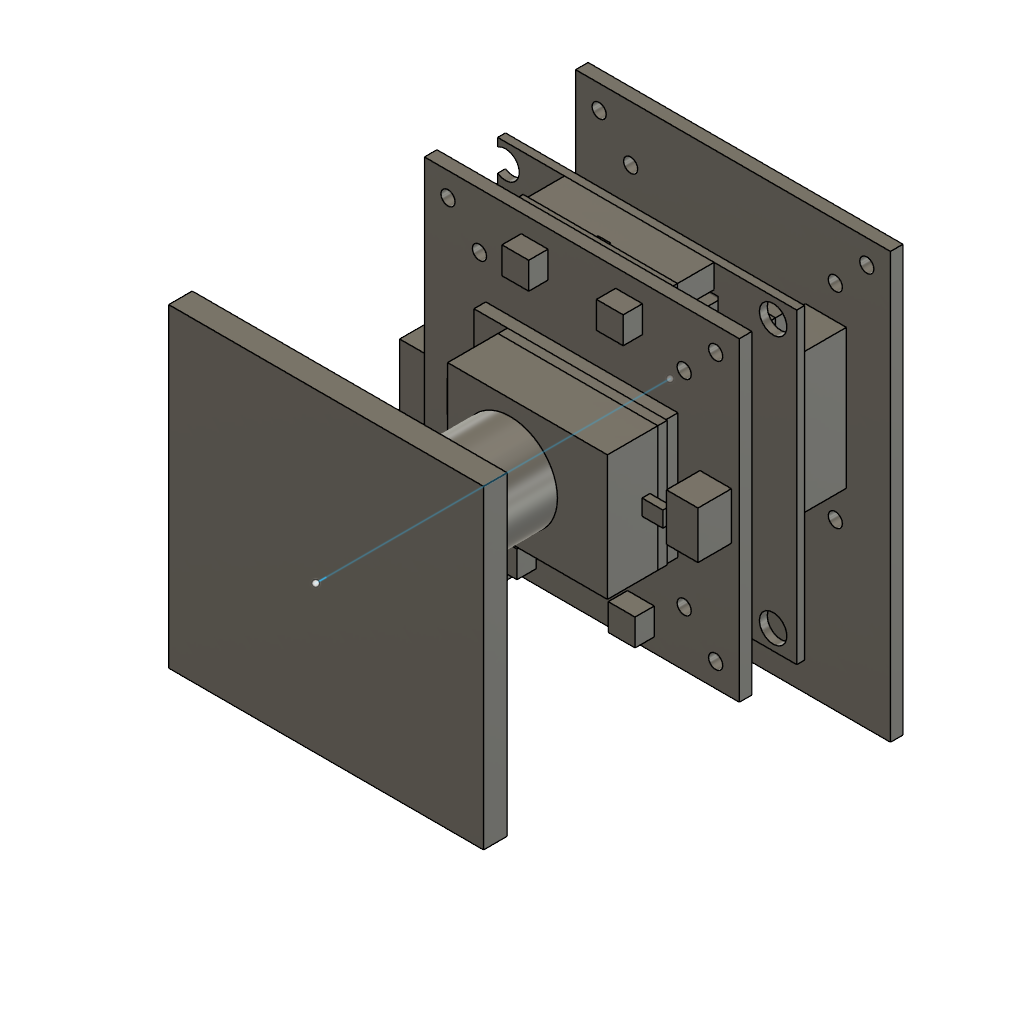
M001_stack_reference (Autodesk Fusion 360 design; units mm, degrees)
part number: 2026-11-26-16-17-13-301
part number: 2026-11-26-16-17-34-578
part number: 2026-11-26-16-17-34-690
part number: 2026-11-26-16-17-34-799
part number: 2026-11-26-16-17-34-957
part number: 2026-11-26-16-17-35-481
part number: 2026-11-26-16-17-36-242
part number: 2026-11-26-16-18-00-802
part number: 2026-11-26-16-54-47-917
part number: 2026-11-26-16-54-48-481
part number: 2026-11-26-16-54-49-083
part number: 2026-11-26-16-54-49-733
part number: 2026-11-26-16-54-51-577
part number: 2026-11-26-16-54-52-375
part number: 2026-11-26-16-54-53-304
part number: 2026-11-26-16-54-54-303
part number: 2026-11-26-17-14-53-023
part number: 2026-11-26-17-14-54-048
part number: 2026-11-26-17-14-55-387
part number: 2026-11-26-17-14-57-169
part number: 2026-11-26-17-14-57-799
part number: 2026-11-26-17-14-58-396
part number: 2026-11-26-17-42-16-332
part number: 2026-11-26-17-42-20-928
part number: 2026-11-26-17-42-21-584
part number: 2026-11-26-17-44-47-207
part number: 2026-11-26-17-44-48-247
part number: 2026-11-26-17-44-49-089
part number: 2026-11-26-17-44-49-752
part number: 2026-11-26-21-12-26-207
part number: 2026-11-26-21-12-26-805
part number: 2026-11-26-21-12-27-357
Autodesk Fusion 360 part; units mm, degrees
ref_plane "작업 평면1" through (0, 0, -1.26) normal (0, 0, 1) x (1, 0, 0) in component "CORE_BOT_KEEPIN"
sketch "스케치1" plane through (0, 0, -1.26) normal (0, 0, 1) x (1, 0, 0) in component "CORE_BOT_KEEPIN"
  line L0 (15, 15) -> (-15, 15)
  line L1 (-15, 15) -> (-15, -15)
  line L2 (-15, -15) -> (15, -15)
  line L3 (15, -15) -> (15, 15)
extrude "돌출1" add sketch "스케치1" along normal blind 1.26 makes body 1 in component "CORE_BOT_KEEPIN"
ref_plane "작업 평면1" through (0, 0, -8) normal (0, 0, 1) x (1, 0, 0) in component "J2_MATED_ENVELOPE"
sketch "스케치1 (2)" plane through (0, 0, -8) normal (0, 0, 1) x (1, 0, 0) in component "J2_MATED_ENVELOPE"
  line L0 (14.4, 8.85) -> (9.2, 8.85)
  line L1 (9.2, 8.85) -> (9.2, -8.85)
  line L2 (9.2, -8.85) -> (14.4, -8.85)
  line L3 (14.4, -8.85) -> (14.4, 8.85)
extrude "돌출1'" add sketch "스케치1 (2)" along normal blind 8 separate body makes body 2 in component "J2_MATED_ENVELOPE"
ref_plane "작업 평면1" through (0, 0, 0) normal (0, 0, 1) x (1, 0, 0) in component "CORE_ENVELOPE_30x30"
sketch "스케치1 (3)" plane through (0, 0, 0) normal (0, 0, 1) x (1, 0, 0) in component "CORE_ENVELOPE_30x30"
  line L0 (15, 15) -> (-15, 15)
  line L1 (-15, 15) -> (-15, -15)
  line L2 (-15, -15) -> (15, -15)
  line L3 (15, -15) -> (15, 15)
  circle A0 centre (13, 13) radius 1
  circle A1 centre (13, -13) radius 1
  circle A2 centre (-13, 13) radius 1
extrude "돌출1''" add sketch "스케치1 (3)" along normal blind 1.6 separate body makes body 3 in component "CORE_ENVELOPE_30x30"
ref_plane "작업 평면1" through (0, 0, 1.6) normal (0, 0, 1) x (1, 0, 0) in component "CORE_TOP_KEEPIN"
sketch "스케치1 (4)" plane through (0, 0, 1.6) normal (0, 0, 1) x (1, 0, 0) in component "CORE_TOP_KEEPIN"
  line L0 (15, 15) -> (-15, 15)
  line L1 (-15, 15) -> (-15, -15)
  line L2 (-15, -15) -> (15, -15)
  line L3 (15, -15) -> (15, 15)
extrude "돌출1'''" add sketch "스케치1 (4)" along normal blind 0.92 separate body makes body 4 in component "CORE_TOP_KEEPIN"
ref_plane "작업 평면1" through (0, 0, 9.6) normal (0, 0, 1) x (1, 0, 0) in component "FRONT_40x40"
sketch "스케치1 (5)" plane through (0, 0, 9.6) normal (0, 0, 1) x (1, 0, 0) in component "FRONT_40x40"
  line L0 (20, 20) -> (-20, 20)
  line L1 (-20, 20) -> (-20, -20)
  line L2 (-20, -20) -> (20, -20)
  line L3 (20, -20) -> (20, 20)
  circle A0 centre (13, 13) radius 0.9
  circle A1 centre (13, -13) radius 0.9
  circle A2 centre (-13, 13) radius 0.9
  circle A3 centre (-17, -17) radius 0.9
  circle A4 centre (17, 17) radius 0.9
  circle A5 centre (17, -17) radius 0.9
  circle A6 centre (-17, 17) radius 0.9
  circle A7 centre (10, 0) radius 0.9
  circle A8 centre (-10, 0) radius 0.9
extrude "돌출1''''" add sketch "스케치1 (5)" along normal blind 1.6 separate body makes body 5 in component "FRONT_40x40"
ref_plane "작업 평면1" through (0, 0, 40.685) normal (0, 0, 1) x (1, 0, 0) in component "WINDOW_PMMA"
sketch "스케치1 (6)" plane through (0, 0, 40.685) normal (0, 0, 1) x (1, 0, 0) in component "WINDOW_PMMA"
  line L0 (20, 20) -> (-20, 20)
  line L1 (-20, 20) -> (-20, -20)
  line L2 (-20, -20) -> (20, -20)
  line L3 (20, -20) -> (20, 20)
extrude "돌출1'''''" add sketch "스케치1 (6)" along normal blind 3 separate body makes body 6 in component "WINDOW_PMMA"
sketch "스케치1 (7)" plane through (0, 0, 0) normal (0, 1, 0) x (1, 0, 0)
  line L0 (0, 0) -> (0, -45)
ref_plane "작업 평면1" through (0, 0, 1.6) normal (0, 0, 1) x (1, 0, 0) in component "J1_MATED_ENVELOPE"
sketch "스케치1 (8)" plane through (0, 0, 1.6) normal (0, 0, 1) x (1, 0, 0) in component "J1_MATED_ENVELOPE"
  line L0 (8.85, 14.41) -> (-8.85, 14.41)
  line L1 (-8.85, 14.41) -> (-8.85, 9.19)
  line L2 (-8.85, 9.19) -> (8.85, 9.19)
  line L3 (8.85, 9.19) -> (8.85, 14.41)
extrude "돌출1''''''" add sketch "스케치1 (8)" along normal blind 8 separate body makes body 7 in component "J1_MATED_ENVELOPE"
ref_plane "작업 평면1" through (0, 0, 11.2) normal (0, 0, 1) x (1, 0, 0) in component "PEDESTAL"
sketch "스케치1 (9)" plane through (0, 0, 11.2) normal (0, 0, 1) x (1, 0, 0) in component "PEDESTAL"
  line L0 (-6.6, -6.6) -> (6.6, -6.6)
  line L1 (6.6, -6.6) -> (6.6, 6.6)
  line L2 (6.6, 6.6) -> (-6.6, 6.6)
  line L3 (-6.6, 6.6) -> (-6.6, -6.6)
  dimension "d117" = 13.2
  dimension "d118" = 13.2
  dimension "d119" = 6.6
  dimension "d120" = 6.6
  measures "d117" horizontal distance of L0.start L0.end
  measures "d118" vertical distance of L0.end L1.end
  measures "d119" horizontal distance of origin L0.start
  measures "d120" vertical distance of origin L0.start
extrude "돌출1'''''''" add sketch "스케치1 (9)" along normal blind 0.75 separate body makes body 8 in component "PEDESTAL"
ref_plane "작업 평면1" through (0, 0, 11.95) normal (0, 0, 1) x (1, 0, 0) in component "SENSOR_BLOCK_BXF4677"
sketch "스케치1 (10)" plane through (0, 0, 11.95) normal (0, 0, 1) x (1, 0, 0) in component "SENSOR_BLOCK_BXF4677"
  line L0 (-6.6, -6.6) -> (6.6, -6.6)
  line L1 (6.6, -6.6) -> (6.6, 6.6)
  line L2 (6.6, 6.6) -> (-6.6, 6.6)
  line L3 (-6.6, 6.6) -> (-6.6, -6.6)
  dimension "d125" = 13.2
  dimension "d126" = 13.2
  dimension "d127" = 6.6
  dimension "d128" = 6.6
  measures "d125" horizontal distance of L0.start L0.end
  measures "d126" vertical distance of L0.end L1.end
  measures "d127" horizontal distance of origin L0.start
  measures "d128" vertical distance of origin L0.start
extrude "돌출1''''''''" add sketch "스케치1 (10)" along normal blind 1.28 separate body makes body 9 in component "SENSOR_BLOCK_BXF4677"
ref_plane "작업 평면1" through (0, 0, 12.35) normal (0, 0, 1) x (1, 0, 0) in component "FPC_3mm"
sketch "스케치1 (11)" plane through (0, 0, 12.35) normal (0, 0, 1) x (1, 0, 0) in component "FPC_3mm"
  line L0 (-3.8, -9.6) -> (3.8, -9.6)
  line L1 (3.8, -9.6) -> (3.8, -6.6)
  line L2 (3.8, -6.6) -> (-3.8, -6.6)
  line L3 (-3.8, -6.6) -> (-3.8, -9.6)
  dimension "d133" = 7.6
  dimension "d134" = 3
  dimension "d135" = 3.8
  dimension "d136" = 9.6
  measures "d133" horizontal distance of L0.start L0.end
  measures "d134" vertical distance of L0.end L1.end
  measures "d135" horizontal distance of origin L0.start
  measures "d136" vertical distance of origin L0.start
extrude "돌출1'''''''''" add sketch "스케치1 (11)" along normal blind 0.12 separate body makes body 10 in component "FPC_3mm"
ref_plane "작업 평면1" through (0, 0, 11.2) normal (0, 0, 1) x (1, 0, 0) in component "DF30_SITE"
sketch "스케치1 (12)" plane through (0, 0, 11.2) normal (0, 0, 1) x (1, 0, 0) in component "DF30_SITE"
  line L0 (-3.8, -14.4) -> (3.8, -14.4)
  line L1 (3.8, -14.4) -> (3.8, -9.6)
  line L2 (3.8, -9.6) -> (-3.8, -9.6)
  line L3 (-3.8, -9.6) -> (-3.8, -14.4)
  dimension "d141" = 7.6
  dimension "d142" = 4.8
  dimension "d143" = 3.8
  dimension "d144" = 14.4
  measures "d141" horizontal distance of L0.start L0.end
  measures "d142" vertical distance of L0.end L1.end
  measures "d143" horizontal distance of origin L0.start
  measures "d144" vertical distance of origin L0.start
extrude "돌출1''''''''''" add sketch "스케치1 (12)" along normal blind 1.15 separate body makes body 11 in component "DF30_SITE"
ref_plane "작업 평면1" through (0, 0, 11.2) normal (0, 0, 1) x (1, 0, 0) in component "LED_A1"
sketch "스케치1 (13)" plane through (0, 0, 11.2) normal (0, 0, 1) x (1, 0, 0) in component "LED_A1"
  line L0 (-7.7, 14.3) -> (-4.3, 14.3)
  line L1 (-4.3, 14.3) -> (-4.3, 17.7)
  line L2 (-4.3, 17.7) -> (-7.7, 17.7)
  line L3 (-7.7, 17.7) -> (-7.7, 14.3)
  dimension "d160" = 3.4
  dimension "d161" = 3.4
  dimension "d162" = 7.7
  dimension "d163" = 14.3
  measures "d160" horizontal distance of L0.start L0.end
  measures "d161" vertical distance of L0.end L1.end
  measures "d162" horizontal distance of origin L0.start
  measures "d163" vertical distance of origin L0.start
extrude "돌출1'''''''''''" add sketch "스케치1 (13)" along normal blind 2.445 separate body makes body 12 in component "LED_A1"
ref_plane "작업 평면1" through (0, 0, 11.2) normal (0, 0, 1) x (1, 0, 0) in component "LED_A2"
sketch "스케치1 (14)" plane through (0, 0, 11.2) normal (0, 0, 1) x (1, 0, 0) in component "LED_A2"
  line L0 (4.3, 14.3) -> (7.7, 14.3)
  line L1 (7.7, 14.3) -> (7.7, 17.7)
  line L2 (7.7, 17.7) -> (4.3, 17.7)
  line L3 (4.3, 17.7) -> (4.3, 14.3)
  dimension "d168" = 3.4
  dimension "d169" = 3.4
  dimension "d170" = 4.3
  dimension "d171" = 14.3
  measures "d168" horizontal distance of L0.start L0.end
  measures "d169" vertical distance of L0.end L1.end
  measures "d170" horizontal distance of origin L0.start
  measures "d171" vertical distance of origin L0.start
extrude "돌출1''''''''''''" add sketch "스케치1 (14)" along normal blind 2.445 separate body makes body 13 in component "LED_A2"
ref_plane "작업 평면1" through (0, 0, 11.2) normal (0, 0, 1) x (1, 0, 0) in component "LED_B1_DNP"
sketch "스케치1 (15)" plane through (0, 0, 11.2) normal (0, 0, 1) x (1, 0, 0) in component "LED_B1_DNP"
  line L0 (-9.2, -18.2) -> (-5.8, -18.2)
  line L1 (-5.8, -18.2) -> (-5.8, -14.8)
  line L2 (-5.8, -14.8) -> (-9.2, -14.8)
  line L3 (-9.2, -14.8) -> (-9.2, -18.2)
  dimension "d176" = 3.4
  dimension "d177" = 3.4
  dimension "d178" = 9.2
  dimension "d179" = 18.2
  measures "d176" horizontal distance of L0.start L0.end
  measures "d177" vertical distance of L0.end L1.end
  measures "d178" horizontal distance of origin L0.start
  measures "d179" vertical distance of origin L0.start
extrude "돌출1'''''''''''''" add sketch "스케치1 (15)" along normal blind 2.445 separate body makes body 14 in component "LED_B1_DNP"
ref_plane "작업 평면1" through (0, 0, 11.2) normal (0, 0, 1) x (1, 0, 0) in component "LED_B2_DNP"
sketch "스케치1 (16)" plane through (0, 0, 11.2) normal (0, 0, 1) x (1, 0, 0) in component "LED_B2_DNP"
  line L0 (5.8, -18.2) -> (9.2, -18.2)
  line L1 (9.2, -18.2) -> (9.2, -14.8)
  line L2 (9.2, -14.8) -> (5.8, -14.8)
  line L3 (5.8, -14.8) -> (5.8, -18.2)
  dimension "d184" = 3.4
  dimension "d185" = 3.4
  dimension "d186" = 5.8
  dimension "d187" = 18.2
  measures "d184" horizontal distance of L0.start L0.end
  measures "d185" vertical distance of L0.end L1.end
  measures "d186" horizontal distance of origin L0.start
  measures "d187" vertical distance of origin L0.start
extrude "돌출1''''''''''''''" add sketch "스케치1 (16)" along normal blind 2.445 separate body makes body 15 in component "LED_B2_DNP"
ref_plane "작업 평면1" through (0, 0, 11.2) normal (0, 0, 1) x (1, 0, 0) in component "HOLDER_SPACER_FRAME"
sketch "스케치1 (17)" plane through (0, 0, 11.2) normal (0, 0, 1) x (1, 0, 0) in component "HOLDER_SPACER_FRAME"
  line L0 (-12.2, -7.95) -> (-4.2, -7.95)
  line L1 (-4.2, -7.95) -> (-4.2, -7.2)
  line L2 (-4.2, -7.2) -> (-7.2, -7.2)
  line L3 (-7.2, -7.2) -> (-7.2, 7.2)
  line L4 (-7.2, 7.2) -> (7.2, 7.2)
  line L5 (7.2, 7.2) -> (7.2, -7.2)
  line L6 (7.2, -7.2) -> (4.2, -7.2)
  line L7 (4.2, -7.2) -> (4.2, -7.95)
  line L8 (4.2, -7.95) -> (12.2, -7.95)
  line L9 (12.2, -7.95) -> (12.2, 7.95)
  line L10 (12.2, 7.95) -> (-12.2, 7.95)
  line L11 (-12.2, 7.95) -> (-12.2, -7.95)
  circle A0 centre (10, 0) radius 0.85
  circle A1 centre (-10, 0) radius 0.85
extrude "돌출1'''''''''''''''" add sketch "스케치1 (17)" along normal blind 1.5 separate body makes body 16 in component "HOLDER_SPACER_FRAME"
ref_plane "작업 평면1" through (0, 0, 12.7) normal (0, 0, 1) x (1, 0, 0) in component "CLA216_ICR"
sketch "스케치1 (18)" plane through (0, 0, 12.7) normal (0, 0, 1) x (1, 0, 0) in component "CLA216_ICR"
  line L0 (-7.95, -7.95) -> (12.35, -7.95)
  line L1 (12.35, -7.95) -> (12.35, 7.95)
  line L2 (12.35, 7.95) -> (-7.95, 7.95)
  line L3 (-7.95, 7.95) -> (-7.95, -7.95)
  line L4 (-7.05, -7.05) -> (7.05, -7.05)
  line L5 (7.05, -7.05) -> (7.05, 7.05)
  line L6 (7.05, 7.05) -> (-7.05, 7.05)
  line L7 (-7.05, 7.05) -> (-7.05, -7.05)
extrude "돌출1''''''''''''''''" add sketch "스케치1 (18)" along normal blind 1.2 separate body makes body 17 in component "CLA216_ICR"
ref_plane "작업 평면2" through (0, 0, 13.9) normal (0, 0, 1) x (1, 0, 0) in component "CLA216_ICR"
sketch "스케치2" plane through (0, 0, 13.9) normal (0, 0, 1) x (1, 0, 0) in component "CLA216_ICR"
  line L0 (-7.95, -7.95) -> (12.35, -7.95)
  line L1 (12.35, -7.95) -> (12.35, 7.95)
  line L2 (12.35, 7.95) -> (-7.95, 7.95)
  line L3 (-7.95, 7.95) -> (-7.95, -7.95)
  circle A0 centre (0, 0) radius 6
extrude "돌출2" add sketch "스케치2" along normal blind 6.4 separate body makes body 18 in component "CLA216_ICR"
ref_plane "작업 평면3" through (0, 0, 12.7) normal (0, 0, 1) x (1, 0, 0) in component "CLA216_ICR"
sketch "스케치3" plane through (0, 0, 12.7) normal (0, 0, 1) x (1, 0, 0) in component "CLA216_ICR"
  line L0 (-12.2, -2) -> (-7.95, -2)
  line L1 (-7.95, -2) -> (-7.95, 2)
  line L2 (-7.95, 2) -> (-12.2, 2)
  line L3 (-12.2, 2) -> (-12.2, -2)
  circle A0 centre (-10, 0) radius 0.85
extrude "돌출3" add sketch "스케치3" along normal blind 3.4 separate body makes body 19 in component "CLA216_ICR"
ref_plane "작업 평면1" through (0, 0, 15.985) normal (0, 0, 1) x (1, 0, 0) in component "LENS_CIL093"
sketch "스케치1 (19)" plane through (0, 0, 15.985) normal (0, 0, 1) x (1, 0, 0) in component "LENS_CIL093"
  circle A0 centre (0, 0) radius 6
extrude "돌출1'''''''''''''''''" add sketch "스케치1 (19)" along normal blind 13.2 separate body makes body 20 in component "LENS_CIL093"
ref_plane "작업 평면2" through (0, 0, 29.185) normal (0, 0, 1) x (1, 0, 0) in component "LENS_CIL093"
sketch "스케치2 (2)" plane through (0, 0, 29.185) normal (0, 0, 1) x (1, 0, 0) in component "LENS_CIL093"
  circle A0 centre (0, 0) radius 7
extrude "돌출2'" add sketch "스케치2 (2)" along normal blind 4.2 separate body makes body 21 in component "LENS_CIL093"
ref_plane "작업 평면3" through (0, 0, 33.385) normal (0, 0, 1) x (1, 0, 0) in component "LENS_CIL093"
sketch "스케치3 (2)" plane through (0, 0, 33.385) normal (0, 0, 1) x (1, 0, 0) in component "LENS_CIL093"
  circle A0 centre (0, 0) radius 9
extrude "돌출3'" add sketch "스케치3 (2)" along normal blind 5.4 separate body makes body 22 in component "LENS_CIL093"
ref_plane "작업 평면4" through (0, 0, 38.785) normal (0, 0, 1) x (1, 0, 0) in component "LENS_CIL093"
sketch "스케치4" plane through (0, 0, 38.785) normal (0, 0, 1) x (1, 0, 0) in component "LENS_CIL093"
  circle A0 centre (0, 0) radius 5
extrude "돌출4" add sketch "스케치4" along normal blind 1.4 separate body makes body 23 in component "LENS_CIL093"
ref_plane "작업 평면1" through (0, 0, 38.785) normal (0, 0, 1) x (1, 0, 0) in component "LIGHT_COLLAR"
sketch "스케치1 (20)" plane through (0, 0, 38.785) normal (0, 0, 1) x (1, 0, 0) in component "LIGHT_COLLAR"
  circle A0 centre (0, 0) radius 10
  circle A1 centre (0, 0) radius 7
extrude "돌출1''''''''''''''''''" add sketch "스케치1 (20)" along normal blind 1.9 separate body makes body 24 in component "LIGHT_COLLAR"
ref_plane "작업 평면1" through (0, 0, 14.9) normal (0, 0, 1) x (1, 0, 0) in component "ICR_LEAD_PATH"
sketch "스케치1 (21)" plane through (0, 0, 14.9) normal (0, 0, 1) x (1, 0, 0) in component "ICR_LEAD_PATH"
  line L0 (12.35, -1) -> (15, -1)
  line L1 (15, -1) -> (15, 1)
  line L2 (15, 1) -> (12.35, 1)
  line L3 (12.35, 1) -> (12.35, -1)
extrude "돌출1'''''''''''''''''''" add sketch "스케치1 (21)" along normal blind 1 separate body makes body 25 in component "ICR_LEAD_PATH"
ref_plane "작업 평면1" through (0, 0, 11.2) normal (0, 0, 1) x (1, 0, 0) in component "J_ICR_SITE"
sketch "스케치1 (22)" plane through (0, 0, 11.2) normal (0, 0, 1) x (1, 0, 0) in component "J_ICR_SITE"
  line L0 (15, -3) -> (19, -3)
  line L1 (19, -3) -> (19, 3)
  line L2 (19, 3) -> (15, 3)
  line L3 (15, 3) -> (15, -3)
extrude "돌출1''''''''''''''''''''" add sketch "스케치1 (22)" along normal blind 4.25 separate body makes body 26 in component "J_ICR_SITE"
ref_plane "작업 평면1" through (0, 0, 2.9) normal (0, 0, 1) x (1, 0, 0) in component "AL_SPREADER_TAB_PX"
sketch "스케치1 (23)" plane through (0, 0, 2.9) normal (0, 0, 1) x (1, 0, 0) in component "AL_SPREADER_TAB_PX"
  line L0 (-18, -19.5) -> (20, -19.5)
  line L1 (20, -19.5) -> (20, 19.5)
  line L2 (20, 19.5) -> (-18, 19.5)
  line L3 (-18, 19.5) -> (-18, -19.5)
  line L4 (-10, 8) -> (10, 8)
  line L5 (10, 8) -> (10, 16)
  line L6 (10, 16) -> (-10, 16)
  line L7 (-10, 16) -> (-10, 8)
  circle A0 centre (13, 13) radius 0.9
  circle A1 centre (13, -13) radius 0.9
  circle A2 centre (-13, 13) radius 0.9
  circle A3 centre (-17, -17) radius 0.9
  circle A4 centre (17, 17) radius 1.75
  circle A5 centre (17, -17) radius 1.75
  circle A6 centre (-17, 17) radius 1.75
extrude "돌출1'''''''''''''''''''''" add sketch "스케치1 (23)" along normal blind 1 separate body contours L0 L1 L2 L3 A6 makes body 27 in component "AL_SPREADER_TAB_PX"
ref_plane "작업 평면1" through (0, 0, 3.9) normal (0, 0, 1) x (1, 0, 0) in component "THERMAL_PILLAR_A"
sketch "스케치1 (24)" plane through (0, 0, 3.9) normal (0, 0, 1) x (1, 0, 0) in component "THERMAL_PILLAR_A"
  line L0 (-9.5, 16.5) -> (9.5, 16.5)
  line L1 (9.5, 16.5) -> (9.5, 19.5)
  line L2 (9.5, 19.5) -> (-9.5, 19.5)
  line L3 (-9.5, 19.5) -> (-9.5, 16.5)
extrude "돌출1''''''''''''''''''''''" add sketch "스케치1 (24)" along normal blind 4.95 separate body makes body 28 in component "THERMAL_PILLAR_A"
ref_plane "작업 평면1" through (0, 0, 3.9) normal (0, 0, 1) x (1, 0, 0) in component "THERMAL_PILLAR_B"
sketch "스케치1 (25)" plane through (0, 0, 3.9) normal (0, 0, 1) x (1, 0, 0) in component "THERMAL_PILLAR_B"
  line L0 (-12, -19.5) -> (-6, -19.5)
  line L1 (-6, -19.5) -> (-6, -13.5)
  line L2 (-6, -13.5) -> (-12, -13.5)
  line L3 (-12, -13.5) -> (-12, -19.5)
  line L4 (6, -19.5) -> (12, -19.5)
  line L5 (12, -19.5) -> (12, -13.5)
  line L6 (12, -13.5) -> (6, -13.5)
  line L7 (6, -13.5) -> (6, -19.5)
extrude "돌출1'''''''''''''''''''''''" add sketch "스케치1 (25)" along normal blind 4.95 separate body makes body 29 at (-10, -15.5, 3.9) makes body 30 at (8, -15.5, 3.9) in component "THERMAL_PILLAR_B"
ref_plane "작업 평면1" through (0, 0, -9.6) normal (0, 0, 1) x (1, 0, 0) in component "CARRIER_40x54"
sketch "스케치1 (26)" plane through (0, 0, -9.6) normal (0, 0, 1) x (1, 0, 0) in component "CARRIER_40x54"
  line L0 (-20, -34) -> (20, -34)
  line L1 (20, -34) -> (20, 20)
  line L2 (20, 20) -> (-20, 20)
  line L3 (-20, 20) -> (-20, -34)
  circle A0 centre (13, 13) radius 0.9
  circle A1 centre (13, -13) radius 0.9
  circle A2 centre (-13, 13) radius 0.9
  circle A3 centre (-17, -17) radius 0.9
  circle A4 centre (17, 17) radius 0.9
  circle A5 centre (-17, 17) radius 0.9
extrude "돌출1''''''''''''''''''''''''" add sketch "스케치1 (26)" along normal blind 1.6 separate body makes body 31 in component "CARRIER_40x54"
ref_plane "작업 평면1" through (0, 0, -8) normal (0, 0, 1) x (1, 0, 0) in component "GH6P_CARRIER_TOP"
sketch "스케치1 (27)" plane through (0, 0, -8) normal (0, 0, 1) x (1, 0, 0) in component "GH6P_CARRIER_TOP"
  line L0 (-19, -30.8) -> (-13.5, -30.8)
  line L1 (-13.5, -30.8) -> (-13.5, -19.3)
  line L2 (-13.5, -19.3) -> (-19, -19.3)
  line L3 (-19, -19.3) -> (-19, -30.8)
extrude "돌출1'''''''''''''''''''''''''" add sketch "스케치1 (27)" along normal blind 4.25 separate body makes body 32 in component "GH6P_CARRIER_TOP"
ref_plane "작업 평면1" through (0, 0, 5.35) normal (0, 0, 1) x (1, 0, 0) in component "GH6P_FRONT_BOT"
sketch "스케치1 (28)" plane through (0, 0, 5.35) normal (0, 0, 1) x (1, 0, 0) in component "GH6P_FRONT_BOT"
  line L0 (-19, -14.7) -> (-13.5, -14.7)
  line L1 (-13.5, -14.7) -> (-13.5, -3.2)
  line L2 (-13.5, -3.2) -> (-19, -3.2)
  line L3 (-19, -3.2) -> (-19, -14.7)
extrude "돌출1''''''''''''''''''''''''''" add sketch "스케치1 (28)" along normal blind 4.25 separate body makes body 33 in component "GH6P_FRONT_BOT"
ref_plane "작업 평면1" through (0, 0, -8) normal (0, 0, 1) x (1, 0, 0) in component "HARNESS_CORRIDOR_MX"
sketch "스케치1 (29)" plane through (0, 0, -8) normal (0, 0, 1) x (1, 0, 0) in component "HARNESS_CORRIDOR_MX"
  line L0 (-24.75, -30.8) -> (-19, -30.8)
  line L1 (-19, -30.8) -> (-19, -3.2)
  line L2 (-19, -3.2) -> (-24.75, -3.2)
  line L3 (-24.75, -3.2) -> (-24.75, -30.8)
extrude "돌출1'''''''''''''''''''''''''''" add sketch "스케치1 (29)" along normal blind 17.6 separate body makes body 34 in component "HARNESS_CORRIDOR_MX"
ref_plane "작업 평면1" through (0, 0, 8.85) normal (0, 0, 1) x (1, 0, 0) in component "INS_PAD_A"
sketch "스케치1 (30)" plane through (0, 0, 8.85) normal (0, 0, 1) x (1, 0, 0) in component "INS_PAD_A"
  line L0 (-9.8, 16.2) -> (9.8, 16.2)
  line L1 (9.8, 16.2) -> (9.8, 19.8)
  line L2 (9.8, 19.8) -> (-9.8, 19.8)
  line L3 (-9.8, 19.8) -> (-9.8, 16.2)
extrude "돌출1''''''''''''''''''''''''''''" add sketch "스케치1 (30)" along normal blind 0.75 separate body makes body 35 in component "INS_PAD_A"
ref_plane "작업 평면1" through (0, 0, 8.85) normal (0, 0, 1) x (1, 0, 0) in component "INS_PAD_B1"
sketch "스케치1 (31)" plane through (0, 0, 8.85) normal (0, 0, 1) x (1, 0, 0) in component "INS_PAD_B1"
  line L0 (-12.3, -19.8) -> (-6, -19.8)
  line L1 (-6, -19.8) -> (-6, -13.2)
  line L2 (-6, -13.2) -> (-12.3, -13.2)
  line L3 (-12.3, -13.2) -> (-12.3, -19.8)
extrude "돌출1'''''''''''''''''''''''''''''" add sketch "스케치1 (31)" along normal blind 0.75 separate body makes body 36 in component "INS_PAD_B1"
ref_plane "작업 평면1" through (0, 0, 8.85) normal (0, 0, 1) x (1, 0, 0) in component "INS_PAD_B2"
sketch "스케치1 (32)" plane through (0, 0, 8.85) normal (0, 0, 1) x (1, 0, 0) in component "INS_PAD_B2"
  line L0 (6, -19.8) -> (12.3, -19.8)
  line L1 (12.3, -19.8) -> (12.3, -13.2)
  line L2 (12.3, -13.2) -> (6, -13.2)
  line L3 (6, -13.2) -> (6, -19.8)
extrude "돌출1''''''''''''''''''''''''''''''" add sketch "스케치1 (32)" along normal blind 0.75 separate body makes body 37 in component "INS_PAD_B2"
ref_plane "작업 평면2" through (0, 0, 8.85) normal (0, 0, 1) x (1, 0, 0) in component "THERMAL_PILLAR_A"
sketch "스케치3 (3)" plane through (0, 0, 8.85) normal (0, 0, 1) x (1, 0, 0) in component "THERMAL_PILLAR_A"
  line L0 (-0.8, 16) -> (0.8, 16)
  line L1 (0.8, 16) -> (0.8, 20)
  line L2 (0.8, 20) -> (-0.8, 20)
  line L3 (-0.8, 20) -> (-0.8, 16)
extrude "RELIEF_SLOT_CUT" cut sketch "스케치3 (3)" against normal blind 0.5 bodies 28 in component "THERMAL_PILLAR_A"
component "CORE_BOT_KEEPIN" placed x (1, 0, 0) y (0, 1, 0) z (0, 0, 1) at (0, 0, 0)
component "J2_MATED_ENVELOPE" placed x (1, 0, 0) y (0, 1, 0) z (0, 0, 1) at (0, 0, 0)
component "CORE_ENVELOPE_30x30" placed x (1, 0, 0) y (0, 1, 0) z (0, 0, 1) at (0, 0, 0)
component "CORE_TOP_KEEPIN" placed x (1, 0, 0) y (0, 1, 0) z (0, 0, 1) at (0, 0, 0)
component "FRONT_40x40" placed x (1, 0, 0) y (0, 1, 0) z (0, 0, 1) at (0, 0, 0)
component "WINDOW_PMMA" placed x (1, 0, 0) y (0, 1, 0) z (0, 0, 1) at (0, 0, 0)
component "J1_MATED_ENVELOPE" placed x (1, 0, 0) y (0, 1, 0) z (0, 0, 1) at (0, 0, 0)
component "PEDESTAL" placed x (1, 0, 0) y (0, 1, 0) z (0, 0, 1) at (0, 0, 0)
component "SENSOR_BLOCK_BXF4677" placed x (1, 0, 0) y (0, 1, 0) z (0, 0, 1) at (0, 0, 0)
component "FPC_3mm" placed x (1, 0, 0) y (0, 1, 0) z (0, 0, 1) at (0, 0, 0)
component "DF30_SITE" placed x (1, 0, 0) y (0, 1, 0) z (0, 0, 1) at (0, 0, 0)
component "LED_A1" placed x (1, 0, 0) y (0, 1, 0) z (0, 0, 1) at (0, 0, 0)
component "LED_A2" placed x (1, 0, 0) y (0, 1, 0) z (0, 0, 1) at (0, 0, 0)
component "LED_B1_DNP" placed x (1, 0, 0) y (0, 1, 0) z (0, 0, 1) at (0, 0, 0)
component "LED_B2_DNP" placed x (1, 0, 0) y (0, 1, 0) z (0, 0, 1) at (0, 0, 0)
component "HOLDER_SPACER_FRAME" placed x (1, 0, 0) y (0, 1, 0) z (0, 0, 1) at (0, 0, 0)
component "CLA216_ICR" placed x (1, 0, 0) y (0, 1, 0) z (0, 0, 1) at (0, 0, 0)
component "LENS_CIL093" placed x (1, 0, 0) y (0, 1, 0) z (0, 0, 1) at (0, 0, 0)
component "LIGHT_COLLAR" placed x (1, 0, 0) y (0, 1, 0) z (0, 0, 1) at (0, 0, 0)
component "ICR_LEAD_PATH" placed x (1, 0, 0) y (0, 1, 0) z (0, 0, 1) at (0, 0, 0)
component "J_ICR_SITE" placed x (1, 0, 0) y (0, 1, 0) z (0, 0, 1) at (0, 0, 0)
component "AL_SPREADER_TAB_PX" placed x (1, 0, 0) y (0, 1, 0) z (0, 0, 1) at (0, 0, 0)
component "THERMAL_PILLAR_A" placed x (1, 0, 0) y (0, 1, 0) z (0, 0, 1) at (0, 0, 0)
component "THERMAL_PILLAR_B" placed x (1, 0, 0) y (0, 1, 0) z (0, 0, 1) at (0, 0, 0)
component "CARRIER_40x54" placed x (1, 0, 0) y (0, 1, 0) z (0, 0, 1) at (0, 0, 0)
component "GH6P_CARRIER_TOP" placed x (1, 0, 0) y (0, 1, 0) z (0, 0, 1) at (0, 0, 0)
component "GH6P_FRONT_BOT" placed x (1, 0, 0) y (0, 1, 0) z (0, 0, 1) at (0, 0, 0)
component "HARNESS_CORRIDOR_MX" placed x (1, 0, 0) y (0, 1, 0) z (0, 0, 1) at (0, 0, 0)
component "INS_PAD_A" placed x (1, 0, 0) y (0, 1, 0) z (0, 0, 1) at (0, 0, 0)
component "INS_PAD_B1" placed x (1, 0, 0) y (0, 1, 0) z (0, 0, 1) at (0, 0, 0)
component "INS_PAD_B2" placed x (1, 0, 0) y (0, 1, 0) z (0, 0, 1) at (0, 0, 0)
equation "carrier_t = 1.6 mm" comment "carrier PCB thickness (assumed)"
equation "core_t = 1.6 mm" comment "core PCB 1.597 measured"
equation "front_t = 1.6 mm" comment "front PCB thickness (assumed)"
equation "btb_h = 8.0 mm" comment "BTB mated height: 8.0 = socket 4.0 + plug body 4.0 (tongue 1.9 inside), R-004 estimate; 4.0 = old M-001 assumption"
equation "core_top_parts = 0.92 mm" comment "core top max part (QFN88) above core top, no-wireless"
equation "core_bot_parts = 1.26 mm" comment "core bottom max part (SOT-23) excl J2"
equation "spr_gap = 1.3 mm" comment "core top to spreader bottom (Seeed frame ceiling 1.3)"
equation "spr_t = 1.0 mm" comment "Al spreader thickness (choice)"
equation "df30_h = 0.9 mm" comment "DF30 mated height 0.9 (R-006 3.3)"
equation "holder_h = 7.6 mm" comment "CLA216-ICR height"
equation "win_gap = 0.5 mm" comment "lens tip to window inner gap"
equation "win_t = 3.0 mm" comment "PMMA window thickness"
equation "d20 = -core_bot_parts"
equation "d22 = core_bot_parts"
equation "d24 = -btb_h"
equation "d26 = btb_h"
equation "d30 = core_t"
equation "d32 = core_t"
equation "d34 = core_top_parts"
equation "d44 = core_t + btb_h"
equation "d46 = front_t"
equation "d64 = core_t + btb_h + front_t + ped_h + img_off + mbfl + l_thr + l_step + l_head + l_dome + win_gap"
equation "d66 = win_t"
equation "d68 = core_t"
equation "d70 = btb_h"
equation "df30_l = 7.6 mm" comment "DF30 site = module stiffener 7.6 (X)"
equation "df30_w = 4.8 mm" comment "DF30 site = module stiffener 4.8 (Y)"
equation "df30_x = 0 mm" comment "DF30 site center X on front top"
equation "df30_y = -( blk / 2 + fpc_len + df30_w / 2 )" comment "DF30 site center Y on front top"
equation "blk = 13.2 mm" comment "BXF4677 sensor block square (R-006 p5, +-0.3)"
equation "ped_h = 0.75 mm" comment "pedestal under sensor block: DF30 mated 0.9 + module stiffener 0.25 - steel 0.4 => FPC flat (R-006 3.3, G2 measure)"
equation "blk_t = 1.28 mm" comment "steel 0.4 + FPC 0.12 + CSP 0.76"
equation "img_off = 0.835 mm" comment "image plane (wafer) above block bottom: 0.4+0.12+(0.76-0.445)"
equation "fpc_len = 3.0 mm" comment "FPC block-to-DF30 stiffener (R-006 p5)"
equation "mbfl = 3.2 mm" comment "CIL093 MBFL 3.2+-0.3 (drawing via R-006)"
equation "ring_w = 3.0 mm" comment "light-block ring wall width at window (>= 2*win_t*tan(25.5deg)=2.9)"
equation "led_s = 3.4 mm" comment "VSMA package square (R-002)"
equation "led_h = 2.445 mm" comment "VSMA1085400 total height (R-007 datasheet Rev1.4)"
equation "d115 = core_t + btb_h + front_t"
equation "d117 = blk"
equation "d118 = blk"
equation "d119 = abs(0 mm - ( blk ) / 2)"
equation "d120 = abs(0 mm - ( blk ) / 2)"
equation "d121 = ped_h"
equation "d123 = core_t + btb_h + front_t + ped_h"
equation "d125 = blk"
equation "d126 = blk"
equation "d127 = abs(0 mm - ( blk ) / 2)"
equation "d128 = abs(0 mm - ( blk ) / 2)"
equation "d129 = blk_t"
equation "d131 = core_t + btb_h + front_t + ped_h + 0.4 mm"
equation "d133 = df30_l"
equation "d134 = fpc_len"
equation "d135 = abs(0 mm - ( df30_l ) / 2)"
equation "d136 = abs(-( blk / 2 + fpc_len / 2 ) - ( fpc_len ) / 2)"
equation "d139 = core_t + btb_h + front_t"
equation "d141 = df30_l"
equation "d142 = df30_w"
equation "d143 = abs(df30_x - ( df30_l ) / 2)"
equation "d144 = abs(df30_y - ( df30_w ) / 2)"
equation "d145 = df30_h + 0.25 mm"
equation "d158 = core_t + btb_h + front_t"
equation "d160 = led_s"
equation "d161 = led_s"
equation "d162 = abs(-6 mm - ( led_s ) / 2)"
equation "d163 = abs(16 mm - ( led_s ) / 2)"
equation "d164 = led_h"
equation "d166 = core_t + btb_h + front_t"
equation "d168 = led_s"
equation "d169 = led_s"
equation "d170 = abs(6 mm - ( led_s ) / 2)"
equation "d171 = abs(16 mm - ( led_s ) / 2)"
equation "d172 = led_h"
equation "d174 = core_t + btb_h + front_t"
equation "d176 = led_s"
equation "d177 = led_s"
equation "d178 = abs(-7.5 mm - ( led_s ) / 2)"
equation "d179 = abs(-16.5 mm - ( led_s ) / 2)"
equation "d180 = led_h"
equation "d182 = core_t + btb_h + front_t"
equation "d184 = led_s"
equation "d185 = led_s"
equation "d186 = abs(7.5 mm - ( led_s ) / 2)"
equation "d187 = abs(-16.5 mm - ( led_s ) / 2)"
equation "d188 = led_h"
equation "sp_t = 1.5 mm" comment "holder spacer frame thickness (K15): window 1.37..1.635"
equation "cav_d = 1.2 mm" comment "CLA216 bottom cavity depth (R-007 read ~1.2-1.25)"
equation "ear_t = 3.4 mm" comment "CLA216 ear thickness (R-007 read)"
equation "l_thr = 13.2 mm" comment "CIL093 rear to step (thread/neck, dia 12)"
equation "l_step = 4.2 mm" comment "CIL093 step dia 14"
equation "l_head = 5.4 mm" comment "CIL093 head dia 18"
equation "l_dome = 1.4 mm" comment "CIL093 glass dome protrusion"
equation "col_t = l_dome + win_gap" comment "light collar: head front face to window inner = l_dome + win_gap"
equation "d198 = core_t + btb_h + front_t"
equation "d200 = sp_t"
equation "d202 = core_t + btb_h + front_t + sp_t"
equation "d204 = cav_d"
equation "d206 = core_t + btb_h + front_t + sp_t + cav_d"
equation "d208 = holder_h - cav_d"
equation "d210 = core_t + btb_h + front_t + sp_t"
equation "d212 = ear_t"
equation "d214 = core_t + btb_h + front_t + ped_h + img_off + mbfl"
equation "d216 = l_thr"
equation "d218 = core_t + btb_h + front_t + ped_h + img_off + mbfl + l_thr"
equation "d220 = l_step"
equation "d222 = core_t + btb_h + front_t + ped_h + img_off + mbfl + l_thr + l_step"
equation "d224 = l_head"
equation "d226 = core_t + btb_h + front_t + ped_h + img_off + mbfl + l_thr + l_step + l_head"
equation "d228 = l_dome"
equation "d230 = core_t + btb_h + front_t + ped_h + img_off + mbfl + l_thr + l_step + l_head"
equation "d232 = col_t"
equation "d234 = core_t + btb_h + front_t + sp_t + 2.2 mm"
equation "d238 = core_t + btb_h + front_t"
equation "d248 = core_t + spr_gap"
equation "d250 = spr_t"
equation "d272 = core_t + spr_gap + spr_t"
equation "d274 = core_t + btb_h - ( core_t + spr_gap + spr_t ) - ins_t"
equation "d276 = core_t + spr_gap + spr_t"
equation "d278 = core_t + btb_h - ( core_t + spr_gap + spr_t ) - ins_t"
equation "gh_h = 4.25 mm" comment "JST SM06B-GHS-TB height - ASSUMED (datasheet not read)"
equation "d281 = -btb_h - carrier_t"
equation "d283 = carrier_t"
equation "d285 = -btb_h"
equation "d287 = gh_h"
equation "d289 = core_t + btb_h - gh_h"
equation "d291 = gh_h"
equation "d293 = -btb_h"
equation "d295 = 2 * btb_h + core_t"
equation "ins_t = 0.75 mm" comment "insulating gap pad design thickness (Tflex P340 1.0t at ~25% compression)"
equation "slot_w = 1.6 mm" comment "pillar A relief slot under TP_A1/TP_A2 gap 0.6"
equation "d301 = core_t + btb_h - ins_t"
equation "d303 = ins_t"
equation "d305 = core_t + btb_h - ins_t"
equation "d307 = ins_t"
equation "d309 = core_t + btb_h - ins_t"
equation "d311 = ins_t"
equation "d313 = core_t + btb_h - ins_t"
equation "d315 = -( 0.5 mm )"
named bodies: "CORE_BOT_KEEPIN", "J2_MATED_ENVELOPE", "CORE_ENVELOPE_30x30", "CORE_TOP_KEEPIN", "FRONT_40x40", "WINDOW_PMMA", "J1_MATED_ENVELOPE", "PEDESTAL", "SENSOR_BLOCK_BXF4677", "FPC_3mm", "DF30_SITE", "LED_A1", "LED_A2", "LED_B1_DNP", "LED_B2_DNP", "HOLDER_SPACER_FRAME", "CLA216_BASE", "CLA216_BODY", "CLA216_EAR_MX", "LENS_THREAD_D12", "LENS_STEP_D14", "LENS_HEAD_D18", "LENS_DOME_D10_PLACEHOLDER", "LIGHT_COLLAR", "ICR_LEAD_STUB", "J_ICR_JST125_2P_SITE", "AL_SPREADER_TAB_PX", "THERMAL_PILLAR_A", "THERMAL_PILLAR_B_1", "THERMAL_PILLAR_B_2", "CARRIER_40x54", "GH6P_CARRIER_TOP", "GH6P_FRONT_BOT", "HARNESS_CORRIDOR_MX", "INS_PAD_A", "INS_PAD_B1", "INS_PAD_B2"
